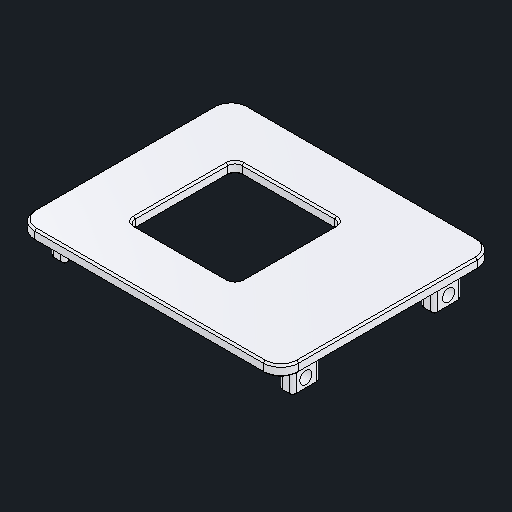
# Autodesk Inventor part: sensor-box-front-panel
Saved by Autodesk Inventor 2027.1 (Build 311270010, 270A)
## iProperties
Created: 2026-10-26
Part Number: sensor-box-front-panel
Material: Generic
Description: Blank removable front panel; side-access M3 mounting; prototype
Document SubType Name: Modeling
Designer: queezz
Density: 1 g/cm^3
Appearance: PTFE
Mass: 14.6317 g
Surface Area: 110.29 cm^2
Volume: 14.6317 cm^3
Author: queezz
Autodesk Inventor part; units mm, degrees
sketch "Panel outline 74 x 60" plane through (0, 0, 0) normal (0, 1, 0) x (-1, 0, 0)
  line L0 (37, -30) -> (-37, -30)
  line L1 (-37, -30) -> (-37, 30)
  line L2 (-37, 30) -> (37, 30)
  line L3 (37, 30) -> (37, -30)
  dimension "d22" = 74
  dimension "d23" = 60
  constraints: 8 end point, 2 parallel, 1 horizontal, 1 perpendicular
  measures "d22" distance of L0.start L0.end
  measures "d23" distance of L0.end L1.end
extrude "Panel face" add sketch "Panel outline 74 x 60" along normal blind 3
fillet "Panel corner radius 5 mm" radius 5 4 edges at (37, 1.5, -30) (37, 1.5, 30) (-37, 1.5, 30) (-37, 1.5, -30)
ref_plane "Left lower removable return profile plane" through (0, 0, -23.7) normal (0, 0, 1) x (1, 0, 0)
sketch "Left lower removable return profile" plane through (0, 0, -23.7) normal (0, 0, 1) x (1, 0, 0)
  line L0 (-34, -8) -> (-30, -8)
  line L1 (-30, -8) -> (-30, 0)
  line L2 (-30, 0) -> (-34, 0)
  line L3 (-34, 0) -> (-34, -8)
  dimension "left_lower_ear_width" = 4
  constraints: 8 end point, 2 parallel, 1 horizontal, 1 perpendicular, 1 vertical
  measures "left_lower_ear_width" distance of L0.start L0.end
extrude "Left lower removable return" add sketch "Left lower removable return profile" along normal blind 7.7
ref_plane "Left upper removable return profile plane" through (0, 0, 16) normal (0, 0, 1) x (1, 0, 0)
sketch "Left upper removable return profile" plane through (0, 0, 16) normal (0, 0, 1) x (1, 0, 0)
  line L0 (-34, -8) -> (-30, -8)
  line L1 (-30, -8) -> (-30, 0)
  line L2 (-30, 0) -> (-34, 0)
  line L3 (-34, 0) -> (-34, -8)
  dimension "left_upper_ear_width" = 4
  constraints: 8 end point, 2 parallel, 1 horizontal, 1 perpendicular, 1 vertical
  measures "left_upper_ear_width" distance of L0.start L0.end
extrude "Left upper removable return" add sketch "Left upper removable return profile" along normal blind 7.7
ref_plane "Right lower removable return profile plane" through (0, 0, -23.7) normal (0, 0, 1) x (1, 0, 0)
sketch "Right lower removable return profile" plane through (0, 0, -23.7) normal (0, 0, 1) x (1, 0, 0)
  line L0 (30, -8) -> (34, -8)
  line L1 (34, -8) -> (34, 0)
  line L2 (34, 0) -> (30, 0)
  line L3 (30, 0) -> (30, -8)
  dimension "right_lower_ear_width" = 4
  constraints: 8 end point, 2 parallel, 1 horizontal, 1 perpendicular, 1 vertical
  measures "right_lower_ear_width" distance of L0.start L0.end
extrude "Right lower removable return" add sketch "Right lower removable return profile" along normal blind 7.7
ref_plane "Right upper removable return profile plane" through (0, 0, 16) normal (0, 0, 1) x (1, 0, 0)
sketch "Right upper removable return profile" plane through (0, 0, 16) normal (0, 0, 1) x (1, 0, 0)
  line L0 (30, -8) -> (34, -8)
  line L1 (34, -8) -> (34, 0)
  line L2 (34, 0) -> (30, 0)
  line L3 (30, 0) -> (30, -8)
  dimension "right_upper_ear_width" = 4
  constraints: 8 end point, 2 parallel, 1 horizontal, 1 perpendicular, 1 vertical
  measures "right_upper_ear_width" distance of L0.start L0.end
extrude "Right upper removable return" add sketch "Right upper removable return profile" along normal blind 7.7
ref_plane "Panel screw access 33.3 plane" through (34, 0, 0) normal (1, 0, 0) x (0, 1, 0)
sketch "Panel screw access 33.3" plane through (34, 0, 0) normal (1, 0, 0) x (0, 1, 0)
  circle A0 centre (-5, -20) radius 1.7
  circle A1 centre (-5, 20) radius 1.7
  dimension "d24" = 3.4
  dimension "d25" = 3.4
  constraints: 2 centre point
  measures "d24" diameter of A0
  measures "d25" diameter of A1
extrude "M3 panel clearance 33.3" cut sketch "Panel screw access 33.3" against normal blind 4
ref_plane "Panel screw access -30.3 plane" through (-30, 0, 0) normal (1, 0, 0) x (0, 1, 0)
sketch "Panel screw access -30.3" plane through (-30, 0, 0) normal (1, 0, 0) x (0, 1, 0)
  circle A0 centre (-5, -20) radius 1.7
  circle A1 centre (-5, 20) radius 1.7
  dimension "d26" = 3.4
  dimension "d27" = 3.4
  constraints: 2 centre point
  measures "d26" diameter of A0
  measures "d27" diameter of A1
extrude "M3 panel clearance -30.3" cut sketch "Panel screw access -30.3" against normal blind 4
chamfer "External face perimeter chamfer 0.5 mm" distance 0.5 angle 45 8 edges at (-35.5355, 3, -28.5355) (0, 3, -30) (-37, 3, 0) (-35.5355, 3, 28.5355) (0, 3, 30) (35.5355, 3, 28.5355) (37, 3, 0) (35.5355, 3, -28.5355)
sketch "Original 30 mm OLED opening" plane through (0, 0, 0) normal (0, 1, 0) x (-1, 0, 0)
  line L0 (20.8911, -15) -> (-9.1089, -15)
  line L1 (-9.1089, -15) -> (-9.1089, 15)
  line L2 (-9.1089, 15) -> (20.8911, 15)
  line L3 (20.8911, 15) -> (20.8911, -15)
  constraints: 8 end point, 2 parallel, 1 horizontal, 1 perpendicular
extrude "Original OLED opening" cut sketch "Original 30 mm OLED opening" along normal blind 3
fillet "Original OLED opening corner radius 2 mm" radius 2 4 edges at (9.1089, 1.5, 15) (9.1089, 1.5, -15) (-20.8911, 1.5, 15) (-20.8911, 1.5, -15)
chamfer "Original OLED opening entry chamfers 0.5 mm" distance 0.5 angle 45 16 edges at (-20.3053, 0, -14.4142) (-20.3053, 3, -14.4142) (-5.8911, 0, -15) (-5.8911, 3, -15) (-20.3053, 0, 14.4142) (-20.3053, 3, 14.4142) (-20.8911, 3, 0) (-20.8911, 0, 0) (8.5232, 0, -14.4142) (8.5232, 3, -14.4142) (9.1089, 0, 0) (9.1089, 3, 0) (8.5232, 0, 14.4142) (8.5232, 3, 14.4142) (-5.8911, 3, 15) (-5.8911, 0, 15)
fillet "Fillet4" radius 1 16 edges at (-30, -4, -23.7) (-30, -4, -16) (-34, -4, -23.7) (-34, -4, -16) (-30, -4, 16) (-34, -4, 16) (-30, -4, 23.7) (-34, -4, 23.7) (30, -4, 16) (34, -4, 16) (34, -4, -23.7) (30, -4, -23.7) (30, -4, -16) (34, -4, -16) (34, -4, 23.7) (30, -4, 23.7)
chamfer "Chamfer3" distance 0.8 angle 45 32 edges at (-30, 0, -19.85) (-30.2929, 0, -23.4071) (-32, 0, -23.7) (-33.7071, 0, -23.4071) (-34, 0, -19.85) (-33.7071, 0, -16.2929) (-32, 0, -16) (-30.2929, 0, -16.2929) (34, 0, -19.85) (33.7071, 0, -23.4071) (32, 0, -23.7) (30.2929, 0, -23.4071) (30, 0, -19.85) (30.2929, 0, -16.2929) (32, 0, -16) (33.7071, 0, -16.2929) (34, 0, 19.85) (33.7071, 0, 16.2929) (32, 0, 16) (30.2929, 0, 16.2929) (30, 0, 19.85) (30.2929, 0, 23.4071) (32, 0, 23.7) (33.7071, 0, 23.4071) (-30, 0, 19.85) (-30.2929, 0, 16.2929) (-32, 0, 16) (-33.7071, 0, 16.2929) (-34, 0, 19.85) (-33.7071, 0, 23.4071) (-32, 0, 23.7) (-30.2929, 0, 23.4071)
chamfer "Chamfer4" distance 0.5 angle 45 40 edges at (0, 0, 30) (-35.5355, 0, 28.5355) (-37, 0, 0) (-35.5355, 0, -28.5355) (0, 0, -30) (35.5355, 0, -28.5355) (37, 0, 0) (35.5355, 0, 28.5355) (33.7071, -8, 23.4071) (34, -8, 19.85) (33.7071, -8, 16.2929) (32, -8, 16) (30.2929, -8, 16.2929) (30, -8, 19.85) (30.2929, -8, 23.4071) (32, -8, 23.7) (34, -8, -19.85) (33.7071, -8, -16.2929) (32, -8, -16) (30.2929, -8, -16.2929) (30, -8, -19.85) (30.2929, -8, -23.4071) (32, -8, -23.7) (33.7071, -8, -23.4071) (-30, -8, -19.85) (-30.2929, -8, -16.2929) (-32, -8, -16) (-33.7071, -8, -16.2929) (-34, -8, -19.85) (-33.7071, -8, -23.4071) (-32, -8, -23.7) (-30.2929, -8, -23.4071) (-30.2929, -8, 16.2929) (-32, -8, 16) (-33.7071, -8, 16.2929) (-34, -8, 19.85) (-33.7071, -8, 23.4071) (-32, -8, 23.7) (-30.2929, -8, 23.4071) (-30, -8, 19.85)
equation "\"d22\" = panel_width"
equation "\"d23\" = panel_height"
equation "\"d0\" = panel_thickness"
equation "\"d24\" = panel_screw_clearance"
equation "\"d25\" = panel_screw_clearance"
equation "\"d26\" = panel_screw_clearance"
equation "\"d27\" = panel_screw_clearance"
equation "\"d31\" = panel_thickness"
equation "\"panel_width\" = 74"
equation "\"panel_height\" = 60"
equation "\"panel_thickness\" = 3"
equation "\"panel_screw_clearance\" = 3.4"
body "Solid1"
